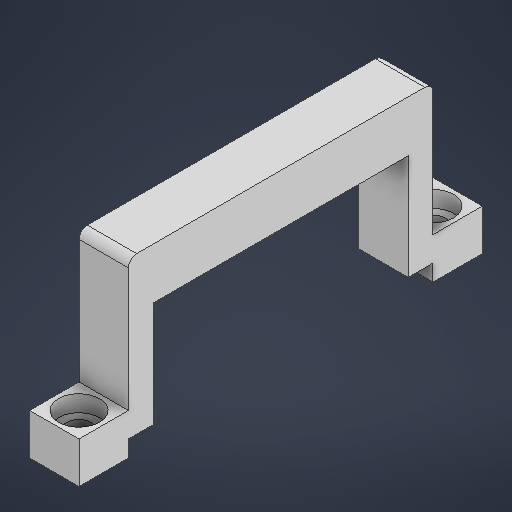
# Autodesk Inventor part: trzyamnie_wylacznika
Saved by Autodesk Inventor 2026.1 (Build 301233020, 233B)
## iProperties
Created: 2026-08-02
Part Number: trzyamnie_wylacznika
Material: Ogólny
Document SubType Name: Modeling
Designer: Nitro
Density: 1 g/cm^3
Appearance: Domyślna
Author: Nitro
Autodesk Inventor part; units mm, degrees
ref_plane "YZ Plane" through (0, 0, 0) normal (1, 0, 0) x (0, 1, 0)
ref_plane "XZ Plane" through (0, 0, 0) normal (0, 1, 0) x (-1, 0, 0)
ref_plane "XY Plane" through (0, 0, 0) normal (0, 0, 1) x (1, 0, 0)
sketch "Szkic1" plane through (0, 0, 0) normal (0, 1, 0) x (-1, 0, 0)
  line L0 (0, 0) -> (6, 0)
  line L1 (6, 0) -> (6, -6)
  line L2 (6, -6) -> (0, -6)
  line L3 (0, -6) -> (0, 0)
  line L4 (0, -43) -> (6, -43)
  line L5 (6, -43) -> (6, -49)
  line L6 (6, -49) -> (0, -49)
  line L7 (0, -49) -> (0, -43)
  dimension "d0" = 6
  dimension "d1" = 6
  dimension "d2" = 6
  dimension "d3" = 6
  dimension "d4" = 37
  constraints: 16 end point, 4 parallel, 2 horizontal, 2 perpendicular
  measures "d0" distance of L1.end L2.end
  measures "d1" distance of L0.end L1.end
  measures "d2" distance of L5.end L6.end
  measures "d3" distance of L4.end L5.end
  measures "d4" distance between parallel lines of L2 L4
extrude "Wyciągnięcie proste1" add sketch "Szkic1" along normal blind 2
sketch "Szkic2" plane through (0, 2, 0) normal (0, 1, 0) x (1, 0, 0)
  line L0 (-6, 6) -> (-6, 0) projected
  line L1 (-6, 0) -> (0, 0)
  line L2 (0, 0) -> (0, 9)
  line L3 (0, 9) -> (-6, 9)
  line L4 (-6, 9) -> (-6, 0)
  line L5 (0, 49) -> (-6, 49) projected
  line L6 (-6, 49) -> (0, 49)
  line L7 (0, 49) -> (0, 40)
  line L8 (0, 40) -> (-6, 40)
  line L9 (-6, 40) -> (-6, 49)
  dimension "d7" = 9
  dimension "d8" = 6
  dimension "d9" = 9
  constraints: 16 end point, 4 parallel, 2 horizontal, 2 perpendicular
  measures "d7" distance of L2.end L1.end
  measures "d8" distance of L7.end L8.end
  measures "d9" distance of L6.end L7.end
extrude "Wyciągnięcie proste2" add sketch "Szkic2" along normal blind 3
sketch "Szkic3" plane through (0, 5, 0) normal (0, 1, 0) x (1, 0, 0)
  line L0 (0, 6) -> (-6, 6) projected
  line L1 (-6, 9) -> (-6, 0) projected
  line L2 (-6, 0) -> (0, 0) projected
  line L3 (0, 0) -> (0, 9) projected
  line L4 (0, 9) -> (-6, 9) projected
  line L5 (-6, 43) -> (0, 43) projected
  line L6 (-6, 40) -> (0, 40) projected
  line L7 (0, 40) -> (0, 49) projected
  line L8 (0, 49) -> (-6, 49) projected
  line L9 (-6, 49) -> (-6, 40) projected
  point P0 (0, 43)
extrude "Wyciągnięcie proste3" add sketch "Szkic3" along normal blind 12 contours L0 L1 L4 L3 | L5 L7 L6 L9
sketch "Szkic4" plane through (0, 17, 0) normal (0, 1, 0) x (1, 0, 0)
  line L0 (-6, 9) -> (-6, 6) projected
  line L1 (-6, 6) -> (0, 6) projected
  line L2 (0, 6) -> (0, 9) projected
  line L3 (0, 9) -> (-6, 9) projected
  line L4 (0, 40) -> (0, 43) projected
  line L5 (0, 43) -> (-6, 43) projected
  line L6 (-6, 43) -> (-6, 40) projected
  line L7 (-6, 40) -> (0, 40) projected
  line L8 (-6, 6) -> (-6, 0) projected
  line L9 (-6, 6) -> (0, 6)
  line L10 (0, 6) -> (0, 43)
  line L11 (0, 43) -> (-6, 43)
  line L12 (-6, 43) -> (-6, 6)
  point P0 (0, 0)
  constraints: 8 end point, 2 parallel, 1 horizontal, 1 perpendicular
extrude "Wyciągnięcie proste4" add sketch "Szkic4" along normal blind 4
sketch "Szkic5" plane through (0, 5, 0) normal (0, 1, 0) x (1, 0, 0)
  line L0 (0, 6) -> (-6, 6) projected
  line L1 (-6, 6) -> (-6, 0) projected
  line L2 (-6, 0) -> (0, 0) projected
  line L3 (0, 0) -> (0, 6) projected
  line L4 (-6, 43) -> (0, 43) projected
  line L5 (0, 43) -> (0, 49) projected
  line L6 (0, 49) -> (-6, 49) projected
  line L7 (-6, 49) -> (-6, 43) projected
  circle A0 centre (-3, 3) radius 1.5
  circle A1 centre (-3, 46) radius 1.5
  dimension "d16" = 3
  dimension "d17" = 3
  constraints: 2 centre point
  measures "d16" diameter of A0
  measures "d17" diameter of A1
extrude "Wyciągnięcie proste5" cut sketch "Szkic5" against normal blind 6 contours A0 | A1
sketch "Szkic6" plane through (0, 5, 0) normal (0, 1, 0) x (1, 0, 0)
  circle A0 centre (-3, 46) radius 1.5 projected
  line L0 (-6, 43) -> (0, 43) projected
  line L1 (0, 43) -> (0, 49) projected
  line L2 (0, 49) -> (-6, 49) projected
  line L3 (-6, 49) -> (-6, 43) projected
  circle A1 centre (-3, 3) radius 1.5 projected
  line L4 (0, 6) -> (-6, 6) projected
  line L5 (-6, 6) -> (-6, 0) projected
  line L6 (-6, 0) -> (0, 0) projected
  line L7 (0, 0) -> (0, 6) projected
  circle A2 centre (-3, 3) radius 2.5
  circle A3 centre (-3, 46) radius 2.5
  dimension "d20" = 5
  dimension "d21" = 5
  constraints: 2 centre point, 2 coincident
  measures "d20" diameter of A2
  measures "d21" diameter of A3
extrude "Wyciągnięcie proste6" cut sketch "Szkic6" against normal blind 2 contours A2 | A3
fillet "Zaokrąglenie1" radius 1 2 edges at (-3, 21, -43) (-3, 21, -6)
sketch "Szkic7" plane through (0, 17, 0) normal (0, -1, 0) x (1, 0, 0)
  line L0 (-6, -40) -> (0, -40) projected
  line L1 (0, -9) -> (0, -40) projected
  line L2 (0, -9) -> (-6, -9) projected
  line L3 (-6, -40) -> (-6, -9) projected
  point P0 (0, 0)
extrude "Wyciągnięcie proste7" add sketch "Szkic7" along normal blind 2.2
